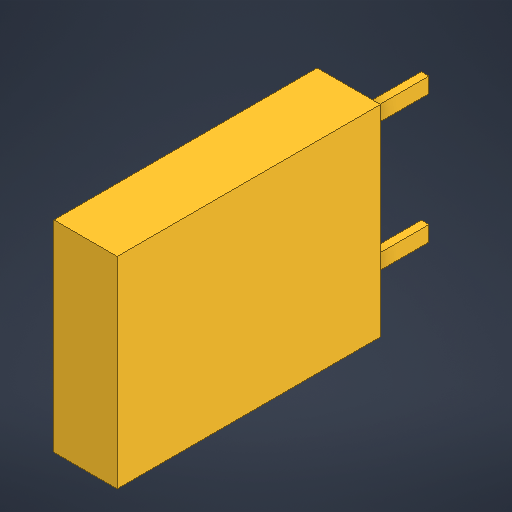
# Autodesk Inventor part: ref_resistor
Saved by Autodesk Inventor 2027.1 (Build 311270010, 270A)
## iProperties
Created: 2026-10-22
Part Number: ref_resistor
Material: 일반
Document SubType Name: Modeling
Designer: sungjun
Density: 1 g/cm^3
Appearance: ref_resistor_c
Author: sungjun
Autodesk Inventor part; units mm, degrees
ref_plane "작업 평면1" through (0, 0, 24.63) normal (0, 0, 1) x (1, 0, 0)
sketch "스케치1" plane through (0, 0, 24.63) normal (0, 0, 1) x (1, 0, 0)
  line L0 (38.8, 46.55) -> (43.8, 46.55)
  line L1 (43.8, 46.55) -> (43.8, 62.45)
  line L2 (43.8, 62.45) -> (38.8, 62.45)
  line L3 (38.8, 62.45) -> (38.8, 46.55)
  constraints: 8 end point, 2 parallel, 1 horizontal, 1 perpendicular
extrude "돌출1" add sketch "스케치1" along normal mid plane 20.8
ref_plane "작업 평면2" through (0, 0, 11.165) normal (0, 0, 1) x (1, 0, 0)
sketch "스케치2" plane through (0, 0, 11.165) normal (0, 0, 1) x (1, 0, 0)
  line L0 (40.9, 48.82) -> (41.5, 48.82)
  line L1 (41.5, 48.82) -> (41.5, 50.02)
  line L2 (41.5, 50.02) -> (40.9, 50.02)
  line L3 (40.9, 50.02) -> (40.9, 48.82)
  constraints: 8 end point, 2 parallel, 1 horizontal, 1 perpendicular
extrude "돌출2" add sketch "스케치2" along normal mid plane 6.13
ref_plane "작업 평면3" through (0, 0, 11.165) normal (0, 0, 1) x (1, 0, 0)
sketch "스케치3" plane through (0, 0, 11.165) normal (0, 0, 1) x (1, 0, 0)
  line L0 (40.9, 58.98) -> (41.5, 58.98)
  line L1 (41.5, 58.98) -> (41.5, 60.18)
  line L2 (41.5, 60.18) -> (40.9, 60.18)
  line L3 (40.9, 60.18) -> (40.9, 58.98)
  constraints: 8 end point, 2 parallel, 1 horizontal, 1 perpendicular
extrude "돌출3" add sketch "스케치3" along normal mid plane 6.13
